Autodesk Fusion 360 part; units mm, degrees
(part 6 of 7)
ref_plane "WorkPlane2" through (0, 0, 38) normal (0, 0, 1) x (1, 0, 0) in component "REFERENCE wall bracket M5x8 100"
sketch "Shank sketch (5)" plane through (0, 0, 38) normal (0, 0, 1) x (1, 0, 0) in component "REFERENCE wall bracket M5x8 100"
  circle A0 centre (228, 52) radius 2.5
  dimension "d2338" = 228
  dimension "d2339" = 52
  dimension "d2340" = 5
  measures "d2338" horizontal distance of origin A0.centre
  measures "d2339" vertical distance of origin A0.centre
  measures "d2340" diameter of A0
extrude "Shank''''" add sketch "Shank sketch (5)" against normal blind 8 bodies 106 in component "REFERENCE wall bracket M5x8 100"
ref_plane "WorkPlane1" through (0, 0, 29) normal (0, 0, 1) x (1, 0, 0) in component "REFERENCE wall bracket T nut 100"
sketch "Nut sketch (5)" plane through (0, 0, 29) normal (0, 0, 1) x (1, 0, 0) in component "REFERENCE wall bracket T nut 100"
  line L0 (223.2, 47.2) -> (232.8, 47.2)
  line L1 (232.8, 47.2) -> (232.8, 56.8)
  line L2 (232.8, 56.8) -> (223.2, 56.8)
  line L3 (223.2, 56.8) -> (223.2, 47.2)
  dimension "d2345" = 223.2
  dimension "d2346" = 47.2
  dimension "d2347" = 9.6
  dimension "d2348" = 9.6
  constraint horizontal L0
  constraint vertical L1
  constraint horizontal L2
  constraint vertical L3
  measures "d2345" horizontal distance of origin L0.start
  measures "d2346" vertical distance of origin L0.start
  measures "d2347" horizontal distance of L0.start L0.end
  measures "d2348" vertical distance of L0.end L1.end
extrude "Nut''''" add sketch "Nut sketch (5)" along normal blind 4 separate body makes body 107 in component "REFERENCE wall bracket T nut 100"
ref_plane "WorkPlane2" through (0, 0, 29) normal (0, 0, 1) x (1, 0, 0) in component "REFERENCE wall bracket T nut 100"
sketch "Thread envelope sketch (28)" plane through (0, 0, 29) normal (0, 0, 1) x (1, 0, 0) in component "REFERENCE wall bracket T nut 100"
  circle A0 centre (228, 52) radius 2.6
  dimension "d2353" = 228
  dimension "d2354" = 52
  dimension "d2355" = 5.2
  measures "d2353" horizontal distance of origin A0.centre
  measures "d2354" vertical distance of origin A0.centre
  measures "d2355" diameter of A0
extrude "Thread envelope'''''''''''''''''''''''''''" cut sketch "Thread envelope sketch (28)" along normal blind 4 bodies 106 in component "REFERENCE wall bracket M5x8 100"
extrude "Extrude2'''''''''''''''''''''''''''" cut sketch "Thread envelope sketch (28)" along normal blind 4 bodies 107 in component "REFERENCE wall bracket T nut 100"
ref_plane "WorkPlane6" through (0, 0, 35) normal (0, 0, 1) x (1, 0, 0) in component "METAL wall standoff 10 - welded or machined"
sketch "Rail attachment clearance sketch (1) (3)" plane through (0, 0, 35) normal (0, 0, 1) x (1, 0, 0) in component "METAL wall standoff 10 - welded or machined"
  circle A0 centre (228, 68) radius 2.75
  dimension "d2362" = 228
  dimension "d2363" = 68
  dimension "d2364" = 5.5
  measures "d2362" horizontal distance of origin A0.centre
  measures "d2363" vertical distance of origin A0.centre
  measures "d2364" diameter of A0
extrude "Rail attachment clearance (1)''" cut sketch "Rail attachment clearance sketch (1) (3)" along normal blind 3 bodies 105 in component "METAL wall standoff 10 - welded or machined"
ref_plane "WorkPlane1" through (0, 0, 38) normal (0, 0, 1) x (1, 0, 0) in component "REFERENCE wall bracket M5x8 101"
sketch "Head sketch (6)" plane through (0, 0, 38) normal (0, 0, 1) x (1, 0, 0) in component "REFERENCE wall bracket M5x8 101"
  circle A0 centre (228, 68) radius 4.75
  dimension "d2369" = 228
  dimension "d2370" = 68
  dimension "d2371" = 9.5
  measures "d2369" horizontal distance of origin A0.centre
  measures "d2370" vertical distance of origin A0.centre
  measures "d2371" diameter of A0
extrude "Head'''''" add sketch "Head sketch (6)" along normal blind 3 separate body makes body 108 in component "REFERENCE wall bracket M5x8 101"
ref_plane "WorkPlane2" through (0, 0, 38) normal (0, 0, 1) x (1, 0, 0) in component "REFERENCE wall bracket M5x8 101"
sketch "Shank sketch (6)" plane through (0, 0, 38) normal (0, 0, 1) x (1, 0, 0) in component "REFERENCE wall bracket M5x8 101"
  circle A0 centre (228, 68) radius 2.5
  dimension "d2376" = 228
  dimension "d2377" = 68
  dimension "d2378" = 5
  measures "d2376" horizontal distance of origin A0.centre
  measures "d2377" vertical distance of origin A0.centre
  measures "d2378" diameter of A0
extrude "Shank'''''" add sketch "Shank sketch (6)" against normal blind 8 bodies 108 in component "REFERENCE wall bracket M5x8 101"
ref_plane "WorkPlane1" through (0, 0, 29) normal (0, 0, 1) x (1, 0, 0) in component "REFERENCE wall bracket T nut 101"
sketch "Nut sketch (6)" plane through (0, 0, 29) normal (0, 0, 1) x (1, 0, 0) in component "REFERENCE wall bracket T nut 101"
  line L0 (223.2, 63.2) -> (232.8, 63.2)
  line L1 (232.8, 63.2) -> (232.8, 72.8)
  line L2 (232.8, 72.8) -> (223.2, 72.8)
  line L3 (223.2, 72.8) -> (223.2, 63.2)
  dimension "d2383" = 223.2
  dimension "d2384" = 63.2
  dimension "d2385" = 9.6
  dimension "d2386" = 9.6
  constraint horizontal L0
  constraint vertical L1
  constraint horizontal L2
  constraint vertical L3
  measures "d2383" horizontal distance of origin L0.start
  measures "d2384" vertical distance of origin L0.start
  measures "d2385" horizontal distance of L0.start L0.end
  measures "d2386" vertical distance of L0.end L1.end
extrude "Nut'''''" add sketch "Nut sketch (6)" along normal blind 4 separate body makes body 109 in component "REFERENCE wall bracket T nut 101"
ref_plane "WorkPlane2" through (0, 0, 29) normal (0, 0, 1) x (1, 0, 0) in component "REFERENCE wall bracket T nut 101"
sketch "Thread envelope sketch (29)" plane through (0, 0, 29) normal (0, 0, 1) x (1, 0, 0) in component "REFERENCE wall bracket T nut 101"
  circle A0 centre (228, 68) radius 2.6
  dimension "d2391" = 228
  dimension "d2392" = 68
  dimension "d2393" = 5.2
  measures "d2391" horizontal distance of origin A0.centre
  measures "d2392" vertical distance of origin A0.centre
  measures "d2393" diameter of A0
extrude "Thread envelope''''''''''''''''''''''''''''" cut sketch "Thread envelope sketch (29)" along normal blind 4 bodies 108 in component "REFERENCE wall bracket M5x8 101"
extrude "Extrude2''''''''''''''''''''''''''''" cut sketch "Thread envelope sketch (29)" along normal blind 4 bodies 109 in component "REFERENCE wall bracket T nut 101"
ref_plane "WorkPlane1" through (0, 0, 35) normal (0, 0, 1) x (1, 0, 0) in component "METAL wall standoff 11 - welded or machined"
sketch "Rail pad sketch (4)" plane through (0, 0, 35) normal (0, 0, 1) x (1, 0, 0) in component "METAL wall standoff 11 - welded or machined"
  line L0 (218, 165) -> (238, 165)
  line L1 (238, 165) -> (238, 195)
  line L2 (238, 195) -> (218, 195)
  line L3 (218, 195) -> (218, 165)
  dimension "d2400" = 218
  dimension "d2401" = 165
  dimension "d2402" = 20
  dimension "d2403" = 30
  constraint horizontal L0
  constraint vertical L1
  constraint horizontal L2
  constraint vertical L3
  measures "d2400" horizontal distance of origin L0.start
  measures "d2401" vertical distance of origin L0.start
  measures "d2402" horizontal distance of L0.start L0.end
  measures "d2403" vertical distance of L0.end L1.end
extrude "Rail pad'''" add sketch "Rail pad sketch (4)" along normal blind 3 separate body makes body 110 in component "METAL wall standoff 11 - welded or machined"
ref_plane "WorkPlane2" through (0, 0, 38) normal (0, 0, 1) x (1, 0, 0) in component "METAL wall standoff 11 - welded or machined"
sketch "Standoff web sketch (4)" plane through (0, 0, 38) normal (0, 0, 1) x (1, 0, 0) in component "METAL wall standoff 11 - welded or machined"
  line L0 (218, 165) -> (221, 165)
  line L1 (221, 165) -> (221, 195)
  line L2 (221, 195) -> (218, 195)
  line L3 (218, 195) -> (218, 165)
  dimension "d2408" = 218
  dimension "d2409" = 165
  dimension "d2410" = 3
  dimension "d2411" = 30
  constraint horizontal L0
  constraint vertical L1
  constraint horizontal L2
  constraint vertical L3
  measures "d2408" horizontal distance of origin L0.start
  measures "d2409" vertical distance of origin L0.start
  measures "d2410" horizontal distance of L0.start L0.end
  measures "d2411" vertical distance of L0.end L1.end
extrude "Standoff web'''" add sketch "Standoff web sketch (4)" along normal blind 4 bodies 110 in component "METAL wall standoff 11 - welded or machined"
ref_plane "WorkPlane3" through (0, 0, 42) normal (0, 0, 1) x (1, 0, 0) in component "METAL wall standoff 11 - welded or machined"
sketch "Wall foot sketch (4)" plane through (0, 0, 42) normal (0, 0, 1) x (1, 0, 0) in component "METAL wall standoff 11 - welded or machined"
  line L0 (196, 165) -> (221, 165)
  line L1 (221, 165) -> (221, 195)
  line L2 (221, 195) -> (196, 195)
  line L3 (196, 195) -> (196, 165)
  dimension "d2416" = 196
  dimension "d2417" = 165
  dimension "d2418" = 25
  dimension "d2419" = 30
  constraint horizontal L0
  constraint vertical L1
  constraint horizontal L2
  constraint vertical L3
  measures "d2416" horizontal distance of origin L0.start
  measures "d2417" vertical distance of origin L0.start
  measures "d2418" horizontal distance of L0.start L0.end
  measures "d2419" vertical distance of L0.end L1.end
extrude "Wall foot'''" add sketch "Wall foot sketch (4)" along normal blind 3 bodies 110 in component "METAL wall standoff 11 - welded or machined"
ref_plane "WorkPlane4" through (0, 0, 42) normal (0, 0, 1) x (1, 0, 0) in component "METAL wall standoff 11 - welded or machined"
sketch "Wall anchor interface sketch (4)" plane through (0, 0, 42) normal (0, 0, 1) x (1, 0, 0) in component "METAL wall standoff 11 - welded or machined"
  circle A0 centre (206, 180) radius 3.25
  dimension "d2424" = 206
  dimension "d2425" = 180
  dimension "d2426" = 6.5
  measures "d2424" horizontal distance of origin A0.centre
  measures "d2425" vertical distance of origin A0.centre
  measures "d2426" diameter of A0
extrude "Wall anchor interface'''" cut sketch "Wall anchor interface sketch (4)" along normal blind 3 bodies 110 in component "METAL wall standoff 11 - welded or machined"
ref_plane "WorkPlane5" through (0, 0, 35) normal (0, 0, 1) x (1, 0, 0) in component "METAL wall standoff 11 - welded or machined"
sketch "Rail attachment clearance sketch (4)" plane through (0, 0, 35) normal (0, 0, 1) x (1, 0, 0) in component "METAL wall standoff 11 - welded or machined"
  circle A0 centre (228, 172) radius 2.75
  dimension "d2431" = 228
  dimension "d2432" = 172
  dimension "d2433" = 5.5
  measures "d2431" horizontal distance of origin A0.centre
  measures "d2432" vertical distance of origin A0.centre
  measures "d2433" diameter of A0
extrude "Rail attachment clearance'''" cut sketch "Rail attachment clearance sketch (4)" along normal blind 3 bodies 110 in component "METAL wall standoff 11 - welded or machined"
ref_plane "WorkPlane1" through (0, 0, 38) normal (0, 0, 1) x (1, 0, 0) in component "REFERENCE wall bracket M5x8 110"
sketch "Head sketch (7)" plane through (0, 0, 38) normal (0, 0, 1) x (1, 0, 0) in component "REFERENCE wall bracket M5x8 110"
  circle A0 centre (228, 172) radius 4.75
  dimension "d2438" = 228
  dimension "d2439" = 172
  dimension "d2440" = 9.5
  measures "d2438" horizontal distance of origin A0.centre
  measures "d2439" vertical distance of origin A0.centre
  measures "d2440" diameter of A0
extrude "Head''''''" add sketch "Head sketch (7)" along normal blind 3 separate body makes body 111 in component "REFERENCE wall bracket M5x8 110"
ref_plane "WorkPlane2" through (0, 0, 38) normal (0, 0, 1) x (1, 0, 0) in component "REFERENCE wall bracket M5x8 110"
sketch "Shank sketch (7)" plane through (0, 0, 38) normal (0, 0, 1) x (1, 0, 0) in component "REFERENCE wall bracket M5x8 110"
  circle A0 centre (228, 172) radius 2.5
  dimension "d2445" = 228
  dimension "d2446" = 172
  dimension "d2447" = 5
  measures "d2445" horizontal distance of origin A0.centre
  measures "d2446" vertical distance of origin A0.centre
  measures "d2447" diameter of A0
extrude "Shank''''''" add sketch "Shank sketch (7)" against normal blind 8 bodies 111 in component "REFERENCE wall bracket M5x8 110"
ref_plane "WorkPlane1" through (0, 0, 29) normal (0, 0, 1) x (1, 0, 0) in component "REFERENCE wall bracket T nut 110"
sketch "Nut sketch (7)" plane through (0, 0, 29) normal (0, 0, 1) x (1, 0, 0) in component "REFERENCE wall bracket T nut 110"
  line L0 (223.2, 167.2) -> (232.8, 167.2)
  line L1 (232.8, 167.2) -> (232.8, 176.8)
  line L2 (232.8, 176.8) -> (223.2, 176.8)
  line L3 (223.2, 176.8) -> (223.2, 167.2)
  dimension "d2452" = 223.2
  dimension "d2453" = 167.2
  dimension "d2454" = 9.6
  dimension "d2455" = 9.6
  constraint horizontal L0
  constraint vertical L1
  constraint horizontal L2
  constraint vertical L3
  measures "d2452" horizontal distance of origin L0.start
  measures "d2453" vertical distance of origin L0.start
  measures "d2454" horizontal distance of L0.start L0.end
  measures "d2455" vertical distance of L0.end L1.end
extrude "Nut''''''" add sketch "Nut sketch (7)" along normal blind 4 separate body makes body 112 in component "REFERENCE wall bracket T nut 110"
ref_plane "WorkPlane2" through (0, 0, 29) normal (0, 0, 1) x (1, 0, 0) in component "REFERENCE wall bracket T nut 110"
sketch "Thread envelope sketch (30)" plane through (0, 0, 29) normal (0, 0, 1) x (1, 0, 0) in component "REFERENCE wall bracket T nut 110"
  circle A0 centre (228, 172) radius 2.6
  dimension "d2460" = 228
  dimension "d2461" = 172
  dimension "d2462" = 5.2
  measures "d2460" horizontal distance of origin A0.centre
  measures "d2461" vertical distance of origin A0.centre
  measures "d2462" diameter of A0
extrude "Thread envelope'''''''''''''''''''''''''''''" cut sketch "Thread envelope sketch (30)" along normal blind 4 bodies 111 in component "REFERENCE wall bracket M5x8 110"
extrude "Extrude2'''''''''''''''''''''''''''''" cut sketch "Thread envelope sketch (30)" along normal blind 4 bodies 112 in component "REFERENCE wall bracket T nut 110"
ref_plane "WorkPlane6" through (0, 0, 35) normal (0, 0, 1) x (1, 0, 0) in component "METAL wall standoff 11 - welded or machined"
sketch "Rail attachment clearance sketch (1) (4)" plane through (0, 0, 35) normal (0, 0, 1) x (1, 0, 0) in component "METAL wall standoff 11 - welded or machined"
  circle A0 centre (228, 188) radius 2.75
  dimension "d2469" = 228
  dimension "d2470" = 188
  dimension "d2471" = 5.5
  measures "d2469" horizontal distance of origin A0.centre
  measures "d2470" vertical distance of origin A0.centre
  measures "d2471" diameter of A0
extrude "Rail attachment clearance (1)'''" cut sketch "Rail attachment clearance sketch (1) (4)" along normal blind 3 bodies 110 in component "METAL wall standoff 11 - welded or machined"
ref_plane "WorkPlane1" through (0, 0, 38) normal (0, 0, 1) x (1, 0, 0) in component "REFERENCE wall bracket M5x8 111"
sketch "Head sketch (8)" plane through (0, 0, 38) normal (0, 0, 1) x (1, 0, 0) in component "REFERENCE wall bracket M5x8 111"
  circle A0 centre (228, 188) radius 4.75
  dimension "d2476" = 228
  dimension "d2477" = 188
  dimension "d2478" = 9.5
  measures "d2476" horizontal distance of origin A0.centre
  measures "d2477" vertical distance of origin A0.centre
  measures "d2478" diameter of A0
extrude "Head'''''''" add sketch "Head sketch (8)" along normal blind 3 separate body makes body 113 in component "REFERENCE wall bracket M5x8 111"
ref_plane "WorkPlane2" through (0, 0, 38) normal (0, 0, 1) x (1, 0, 0) in component "REFERENCE wall bracket M5x8 111"
sketch "Shank sketch (8)" plane through (0, 0, 38) normal (0, 0, 1) x (1, 0, 0) in component "REFERENCE wall bracket M5x8 111"
  circle A0 centre (228, 188) radius 2.5
  dimension "d2483" = 228
  dimension "d2484" = 188
  dimension "d2485" = 5
  measures "d2483" horizontal distance of origin A0.centre
  measures "d2484" vertical distance of origin A0.centre
  measures "d2485" diameter of A0
extrude "Shank'''''''" add sketch "Shank sketch (8)" against normal blind 8 bodies 113 in component "REFERENCE wall bracket M5x8 111"
ref_plane "WorkPlane1" through (0, 0, 29) normal (0, 0, 1) x (1, 0, 0) in component "REFERENCE wall bracket T nut 111"
sketch "Nut sketch (8)" plane through (0, 0, 29) normal (0, 0, 1) x (1, 0, 0) in component "REFERENCE wall bracket T nut 111"
  line L0 (223.2, 183.2) -> (232.8, 183.2)
  line L1 (232.8, 183.2) -> (232.8, 192.8)
  line L2 (232.8, 192.8) -> (223.2, 192.8)
  line L3 (223.2, 192.8) -> (223.2, 183.2)
  dimension "d2490" = 223.2
  dimension "d2491" = 183.2
  dimension "d2492" = 9.6
  dimension "d2493" = 9.6
  constraint horizontal L0
  constraint vertical L1
  constraint horizontal L2
  constraint vertical L3
  measures "d2490" horizontal distance of origin L0.start
  measures "d2491" vertical distance of origin L0.start
  measures "d2492" horizontal distance of L0.start L0.end
  measures "d2493" vertical distance of L0.end L1.end
extrude "Nut'''''''" add sketch "Nut sketch (8)" along normal blind 4 separate body makes body 114 in component "REFERENCE wall bracket T nut 111"
ref_plane "WorkPlane2" through (0, 0, 29) normal (0, 0, 1) x (1, 0, 0) in component "REFERENCE wall bracket T nut 111"
sketch "Thread envelope sketch (31)" plane through (0, 0, 29) normal (0, 0, 1) x (1, 0, 0) in component "REFERENCE wall bracket T nut 111"
  circle A0 centre (228, 188) radius 2.6
  dimension "d2498" = 228
  dimension "d2499" = 188
  dimension "d2500" = 5.2
  measures "d2498" horizontal distance of origin A0.centre
  measures "d2499" vertical distance of origin A0.centre
  measures "d2500" diameter of A0
extrude "Thread envelope''''''''''''''''''''''''''''''" cut sketch "Thread envelope sketch (31)" along normal blind 4 bodies 113 in component "REFERENCE wall bracket M5x8 111"
extrude "Extrude2''''''''''''''''''''''''''''''" cut sketch "Thread envelope sketch (31)" along normal blind 4 bodies 114 in component "REFERENCE wall bracket T nut 111"
component "Panel lower left" placed x (1, 0, 0) y (0, 1, 0) z (0, 0, 1) at (0, 0, 0)
component "Panel lower right" placed x (1, 0, 0) y (0, 1, 0) z (0, 0, 1) at (0, 0, 0)
component "Panel upper left" placed x (1, 0, 0) y (0, 1, 0) z (0, 0, 1) at (0, 0, 0)
component "Panel upper right" placed x (1, 0, 0) y (0, 1, 0) z (0, 0, 1) at (0, 0, 0)
component "PRINT horizontal alignment key L" placed x (1, 0, 0) y (0, 1, 0) z (0, 0, 1) at (0, 0, 0)
component "PRINT horizontal alignment key R" placed x (1, 0, 0) y (0, 1, 0) z (0, 0, 1) at (0, 0, 0)
component "PRINT vertical alignment key B" placed x (1, 0, 0) y (0, 1, 0) z (0, 0, 1) at (0, 0, 0)
component "PRINT vertical alignment key T" placed x (1, 0, 0) y (0, 1, 0) z (0, 0, 1) at (0, 0, 0)
component "Vertical rail 0 - nominal 2020 slot-6 envelope" placed x (1, 0, 0) y (0, 1, 0) z (0, 0, 1) at (0, 0, 0)
component "Vertical rail 1 - nominal 2020 slot-6 envelope" placed x (1, 0, 0) y (0, 1, 0) z (0, 0, 1) at (0, 0, 0)
component "Vertical rail 2 - nominal 2020 slot-6 envelope" placed x (1, 0, 0) y (0, 1, 0) z (0, 0, 1) at (0, 0, 0)
component "Horizontal tie 00 - nominal 2020 slot-6 envelope" placed x (1, 0, 0) y (0, 1, 0) z (0, 0, 1) at (0, 0, 0)
component "Horizontal tie 10 - nominal 2020 slot-6 envelope" placed x (1, 0, 0) y (0, 1, 0) z (0, 0, 1) at (0, 0, 0)
component "Horizontal tie 01 - nominal 2020 slot-6 envelope" placed x (1, 0, 0) y (0, 1, 0) z (0, 0, 1) at (0, 0, 0)
component "Horizontal tie 11 - nominal 2020 slot-6 envelope" placed x (1, 0, 0) y (0, 1, 0) z (0, 0, 1) at (0, 0, 0)
component "METAL cap 00" placed x (1, 0, 0) y (0, 1, 0) z (0, 0, 1) at (0, 0, 0)
component "PRINT rear bearing seat 00" placed x (1, 0, 0) y (0, 1, 0) z (0, 0, 1) at (0, 0, 0)
component "METAL stepped compression spacer 00" placed x (1, 0, 0) y (0, 1, 0) z (0, 0, 1) at (0, 0, 0)
component "REFERENCE M5 screw 00 - length follows stack" placed x (1, 0, 0) y (0, 1, 0) z (0, 0, 1) at (0, 0, 0)
component "REFERENCE M5 slot-6 T nut 00" placed x (1, 0, 0) y (0, 1, 0) z (0, 0, 1) at (0, 0, 0)
component "METAL cap 01" placed x (1, 0, 0) y (0, 1, 0) z (0, 0, 1) at (0, 0, 0)
component "PRINT rear bearing seat 01" placed x (1, 0, 0) y (0, 1, 0) z (0, 0, 1) at (0, 0, 0)
component "METAL stepped compression spacer 01" placed x (1, 0, 0) y (0, 1, 0) z (0, 0, 1) at (0, 0, 0)
component "REFERENCE M5 screw 01 - length follows stack" placed x (1, 0, 0) y (0, 1, 0) z (0, 0, 1) at (0, 0, 0)
component "REFERENCE M5 slot-6 T nut 01" placed x (1, 0, 0) y (0, 1, 0) z (0, 0, 1) at (0, 0, 0)
component "METAL cap 02" placed x (1, 0, 0) y (0, 1, 0) z (0, 0, 1) at (0, 0, 0)
component "PRINT rear bearing seat 02" placed x (1, 0, 0) y (0, 1, 0) z (0, 0, 1) at (0, 0, 0)
component "METAL stepped compression spacer 02" placed x (1, 0, 0) y (0, 1, 0) z (0, 0, 1) at (0, 0, 0)
component "REFERENCE M5 screw 02 - length follows stack" placed x (1, 0, 0) y (0, 1, 0) z (0, 0, 1) at (0, 0, 0)
component "REFERENCE M5 slot-6 T nut 02" placed x (1, 0, 0) y (0, 1, 0) z (0, 0, 1) at (0, 0, 0)
component "METAL cap 10" placed x (1, 0, 0) y (0, 1, 0) z (0, 0, 1) at (0, 0, 0)
component "PRINT rear bearing seat 10" placed x (1, 0, 0) y (0, 1, 0) z (0, 0, 1) at (0, 0, 0)
component "METAL stepped compression spacer 10" placed x (1, 0, 0) y (0, 1, 0) z (0, 0, 1) at (0, 0, 0)
component "REFERENCE M5 screw 10 - length follows stack" placed x (1, 0, 0) y (0, 1, 0) z (0, 0, 1) at (0, 0, 0)
component "REFERENCE M5 slot-6 T nut 10" placed x (1, 0, 0) y (0, 1, 0) z (0, 0, 1) at (0, 0, 0)
component "METAL cap 11" placed x (1, 0, 0) y (0, 1, 0) z (0, 0, 1) at (0, 0, 0)
component "PRINT rear bearing seat 11" placed x (1, 0, 0) y (0, 1, 0) z (0, 0, 1) at (0, 0, 0)
component "METAL stepped compression spacer 11" placed x (1, 0, 0) y (0, 1, 0) z (0, 0, 1) at (0, 0, 0)
component "REFERENCE M5 screw 11 - length follows stack" placed x (1, 0, 0) y (0, 1, 0) z (0, 0, 1) at (0, 0, 0)
component "REFERENCE M5 slot-6 T nut 11" placed x (1, 0, 0) y (0, 1, 0) z (0, 0, 1) at (0, 0, 0)
component "METAL cap 12" placed x (1, 0, 0) y (0, 1, 0) z (0, 0, 1) at (0, 0, 0)
component "PRINT rear bearing seat 12" placed x (1, 0, 0) y (0, 1, 0) z (0, 0, 1) at (0, 0, 0)
component "METAL stepped compression spacer 12" placed x (1, 0, 0) y (0, 1, 0) z (0, 0, 1) at (0, 0, 0)
component "REFERENCE M5 screw 12 - length follows stack" placed x (1, 0, 0) y (0, 1, 0) z (0, 0, 1) at (0, 0, 0)
component "REFERENCE M5 slot-6 T nut 12" placed x (1, 0, 0) y (0, 1, 0) z (0, 0, 1) at (0, 0, 0)
component "METAL cap 20" placed x (1, 0, 0) y (0, 1, 0) z (0, 0, 1) at (0, 0, 0)
component "PRINT rear bearing seat 20" placed x (1, 0, 0) y (0, 1, 0) z (0, 0, 1) at (0, 0, 0)
component "METAL stepped compression spacer 20" placed x (1, 0, 0) y (0, 1, 0) z (0, 0, 1) at (0, 0, 0)
component "REFERENCE M5 screw 20 - length follows stack" placed x (1, 0, 0) y (0, 1, 0) z (0, 0, 1) at (0, 0, 0)
component "REFERENCE M5 slot-6 T nut 20" placed x (1, 0, 0) y (0, 1, 0) z (0, 0, 1) at (0, 0, 0)
component "METAL cap 21" placed x (1, 0, 0) y (0, 1, 0) z (0, 0, 1) at (0, 0, 0)
component "PRINT rear bearing seat 21" placed x (1, 0, 0) y (0, 1, 0) z (0, 0, 1) at (0, 0, 0)
component "METAL stepped compression spacer 21" placed x (1, 0, 0) y (0, 1, 0) z (0, 0, 1) at (0, 0, 0)
component "REFERENCE M5 screw 21 - length follows stack" placed x (1, 0, 0) y (0, 1, 0) z (0, 0, 1) at (0, 0, 0)
component "REFERENCE M5 slot-6 T nut 21" placed x (1, 0, 0) y (0, 1, 0) z (0, 0, 1) at (0, 0, 0)
component "METAL cap 22" placed x (1, 0, 0) y (0, 1, 0) z (0, 0, 1) at (0, 0, 0)
component "PRINT rear bearing seat 22" placed x (1, 0, 0) y (0, 1, 0) z (0, 0, 1) at (0, 0, 0)
component "METAL stepped compression spacer 22" placed x (1, 0, 0) y (0, 1, 0) z (0, 0, 1) at (0, 0, 0)
component "REFERENCE M5 screw 22 - length follows stack" placed x (1, 0, 0) y (0, 1, 0) z (0, 0, 1) at (0, 0, 0)
component "REFERENCE M5 slot-6 T nut 22" placed x (1, 0, 0) y (0, 1, 0) z (0, 0, 1) at (0, 0, 0)
component "METAL rear splice plate 00" placed x (1, 0, 0) y (0, 1, 0) z (0, 0, 1) at (0, 0, 0)
component "REFERENCE rear join screw 000" placed x (1, 0, 0) y (0, 1, 0) z (0, 0, 1) at (0, 0, 0)
component "REFERENCE rear T nut 000" placed x (1, 0, 0) y (0, 1, 0) z (0, 0, 1) at (0, 0, 0)
component "REFERENCE rear join screw 001" placed x (1, 0, 0) y (0, 1, 0) z (0, 0, 1) at (0, 0, 0)
component "REFERENCE rear T nut 001" placed x (1, 0, 0) y (0, 1, 0) z (0, 0, 1) at (0, 0, 0)
component "METAL rear splice plate 10" placed x (1, 0, 0) y (0, 1, 0) z (0, 0, 1) at (0, 0, 0)
component "REFERENCE rear join screw 100" placed x (1, 0, 0) y (0, 1, 0) z (0, 0, 1) at (0, 0, 0)
component "REFERENCE rear T nut 100" placed x (1, 0, 0) y (0, 1, 0) z (0, 0, 1) at (0, 0, 0)
component "REFERENCE rear join screw 101" placed x (1, 0, 0) y (0, 1, 0) z (0, 0, 1) at (0, 0, 0)
component "REFERENCE rear T nut 101" placed x (1, 0, 0) y (0, 1, 0) z (0, 0, 1) at (0, 0, 0)
component "REFERENCE rear join screw 102" placed x (1, 0, 0) y (0, 1, 0) z (0, 0, 1) at (0, 0, 0)
component "REFERENCE rear T nut 102" placed x (1, 0, 0) y (0, 1, 0) z (0, 0, 1) at (0, 0, 0)
component "METAL rear splice plate 20" placed x (1, 0, 0) y (0, 1, 0) z (0, 0, 1) at (0, 0, 0)
component "REFERENCE rear join screw 200" placed x (1, 0, 0) y (0, 1, 0) z (0, 0, 1) at (0, 0, 0)
component "REFERENCE rear T nut 200" placed x (1, 0, 0) y (0, 1, 0) z (0, 0, 1) at (0, 0, 0)
component "REFERENCE rear join screw 201" placed x (1, 0, 0) y (0, 1, 0) z (0, 0, 1) at (0, 0, 0)
component "REFERENCE rear T nut 201" placed x (1, 0, 0) y (0, 1, 0) z (0, 0, 1) at (0, 0, 0)
component "METAL rear splice plate 01" placed x (1, 0, 0) y (0, 1, 0) z (0, 0, 1) at (0, 0, 0)
component "REFERENCE rear join screw 010" placed x (1, 0, 0) y (0, 1, 0) z (0, 0, 1) at (0, 0, 0)
component "REFERENCE rear T nut 010" placed x (1, 0, 0) y (0, 1, 0) z (0, 0, 1) at (0, 0, 0)
component "REFERENCE rear join screw 011" placed x (1, 0, 0) y (0, 1, 0) z (0, 0, 1) at (0, 0, 0)
component "REFERENCE rear T nut 011" placed x (1, 0, 0) y (0, 1, 0) z (0, 0, 1) at (0, 0, 0)
component "METAL rear splice plate 11" placed x (1, 0, 0) y (0, 1, 0) z (0, 0, 1) at (0, 0, 0)
component "REFERENCE rear join screw 110" placed x (1, 0, 0) y (0, 1, 0) z (0, 0, 1) at (0, 0, 0)
component "REFERENCE rear T nut 110" placed x (1, 0, 0) y (0, 1, 0) z (0, 0, 1) at (0, 0, 0)
component "REFERENCE rear join screw 111" placed x (1, 0, 0) y (0, 1, 0) z (0, 0, 1) at (0, 0, 0)
component "REFERENCE rear T nut 111" placed x (1, 0, 0) y (0, 1, 0) z (0, 0, 1) at (0, 0, 0)
component "REFERENCE rear join screw 112" placed x (1, 0, 0) y (0, 1, 0) z (0, 0, 1) at (0, 0, 0)
component "REFERENCE rear T nut 112" placed x (1, 0, 0) y (0, 1, 0) z (0, 0, 1) at (0, 0, 0)
component "METAL rear splice plate 21" placed x (1, 0, 0) y (0, 1, 0) z (0, 0, 1) at (0, 0, 0)
component "REFERENCE rear join screw 210" placed x (1, 0, 0) y (0, 1, 0) z (0, 0, 1) at (0, 0, 0)
component "REFERENCE rear T nut 210" placed x (1, 0, 0) y (0, 1, 0) z (0, 0, 1) at (0, 0, 0)
component "REFERENCE rear join screw 211" placed x (1, 0, 0) y (0, 1, 0) z (0, 0, 1) at (0, 0, 0)
component "REFERENCE rear T nut 211" placed x (1, 0, 0) y (0, 1, 0) z (0, 0, 1) at (0, 0, 0)
component "METAL wall standoff 00 - welded or machined" placed x (1, 0, 0) y (0, 1, 0) z (0, 0, 1) at (0, 0, 0)
component "REFERENCE wall bracket M5x8 000" placed x (1, 0, 0) y (0, 1, 0) z (0, 0, 1) at (0, 0, 0)
component "REFERENCE wall bracket T nut 000" placed x (1, 0, 0) y (0, 1, 0) z (0, 0, 1) at (0, 0, 0)
component "REFERENCE wall bracket M5x8 001" placed x (1, 0, 0) y (0, 1, 0) z (0, 0, 1) at (0, 0, 0)
component "REFERENCE wall bracket T nut 001" placed x (1, 0, 0) y (0, 1, 0) z (0, 0, 1) at (0, 0, 0)
component "METAL wall standoff 01 - welded or machined" placed x (1, 0, 0) y (0, 1, 0) z (0, 0, 1) at (0, 0, 0)
component "REFERENCE wall bracket M5x8 010" placed x (1, 0, 0) y (0, 1, 0) z (0, 0, 1) at (0, 0, 0)
component "REFERENCE wall bracket T nut 010" placed x (1, 0, 0) y (0, 1, 0) z (0, 0, 1) at (0, 0, 0)
component "REFERENCE wall bracket M5x8 011" placed x (1, 0, 0) y (0, 1, 0) z (0, 0, 1) at (0, 0, 0)
component "REFERENCE wall bracket T nut 011" placed x (1, 0, 0) y (0, 1, 0) z (0, 0, 1) at (0, 0, 0)
component "METAL wall standoff 10 - welded or machined" placed x (1, 0, 0) y (0, 1, 0) z (0, 0, 1) at (0, 0, 0)
component "REFERENCE wall bracket M5x8 100" placed x (1, 0, 0) y (0, 1, 0) z (0, 0, 1) at (0, 0, 0)
component "REFERENCE wall bracket T nut 100" placed x (1, 0, 0) y (0, 1, 0) z (0, 0, 1) at (0, 0, 0)
component "REFERENCE wall bracket M5x8 101" placed x (1, 0, 0) y (0, 1, 0) z (0, 0, 1) at (0, 0, 0)
component "REFERENCE wall bracket T nut 101" placed x (1, 0, 0) y (0, 1, 0) z (0, 0, 1) at (0, 0, 0)
component "METAL wall standoff 11 - welded or machined" placed x (1, 0, 0) y (0, 1, 0) z (0, 0, 1) at (0, 0, 0)
component "REFERENCE wall bracket M5x8 110" placed x (1, 0, 0) y (0, 1, 0) z (0, 0, 1) at (0, 0, 0)
component "REFERENCE wall bracket T nut 110" placed x (1, 0, 0) y (0, 1, 0) z (0, 0, 1) at (0, 0, 0)
component "REFERENCE wall bracket M5x8 111" placed x (1, 0, 0) y (0, 1, 0) z (0, 0, 1) at (0, 0, 0)
component "REFERENCE wall bracket T nut 111" placed x (1, 0, 0) y (0, 1, 0) z (0, 0, 1) at (0, 0, 0)
equation "columns = 6" comment "Even integer 4..14; each cell is 20 mm"
equation "rows = 6" comment "Even integer 4..14"
equation "pitch = 20 mm" comment "Keep for dense SKADIS compatible lattice"
equation "panelWidth = columns * pitch" comment "Nominal module pitch X"
equation "panelHeight = rows * pitch" comment "Nominal module pitch Y"
equation "seamGap = 0.2 mm" comment "Physical envelope shrinks around fixed lattice"
equation "boardThickness = 5 mm" comment "Fit-test with real hooks"
equation "slotWidth = 5 mm" comment "Minimum throat width"
equation "slotHeight = 15 mm" comment "Minimum throat height"
equation "entryRadius = 0.4 mm" comment "Front slot and perimeter edge rounding"
equation "cornerRadius = 6 mm" comment "Plan-view panel corner rounding"
equation "hookClearance = 10 mm" comment "PROVISIONAL: board rear to front of extrusion"
equation "frameZ = boardThickness + hookClearance" comment "Front extrusion datum"
equation "mountInset = 12 mm" comment "Exterior node inset from outside module edge"
equation "mountBore = 8.4 mm" comment "Clearance around 8 mm metal shoulder"
equation "capDiameter = 18 mm" comment "Visible decorative mounting disk"
equation "capThickness = 2 mm" comment "Metal clamping cap / washer"
equation "seatThickness = 2 mm" comment "Printed rear bearing washer"
equation "screwDiameter = 5 mm" comment "Nominal M5 reference, threads omitted"
equation "screwClearance = 5.5 mm" comment "Cap and spacer bore"
equation "keyWidth = 4 mm" comment "Registration key corridor width"
equation "keyThickness = 2 mm" comment "Rear removable key body"
equation "keyPegDiameter = 3 mm" comment "Rear locating peg"
equation "keySocketDiameter = 3.4 mm" comment "0.2 mm radial starting fit"
equation "keyPegHeight = 0.8 mm" comment "Peg penetration"
equation "keySocketDepth = 1 mm" comment "Blind locating pocket"
equation "llLeft = 1" comment "0 internal / 1 finished; full cell border and inset mounting"
equation "llRight = 0" comment "0 internal / 1 finished; full cell border and inset mounting"
equation "llBottom = 1" comment "0 internal / 1 finished; full cell border and inset mounting"
equation "llTop = 0" comment "0 internal / 1 finished; full cell border and inset mounting"
equation "d31 = abs(( 0 mm ) + seamGap / 2)"
equation "d32 = abs(( 0 mm ) + seamGap / 2)"
equation "d33 = panelWidth - seamGap"
equation "d34 = panelHeight - seamGap"
equation "d35 = boardThickness"
equation "d38 = cornerRadius"
equation "d39 = slotWidth"
equation "d40 = slotHeight - slotWidth"
equation "d42 = pitch / 2"
equation "d43 = abs(( 0 mm ) + pitch / 4 + pitch * ( llLeft + 1 ))"
equation "d44 = abs(( ( 0 mm ) + pitch / 2 + pitch * llBottom ) - ( slotHeight - slotWidth ) / 2)"
equation "d45 = boardThickness"
equation "d47 = columns - llLeft - llRight - 1"
equation "d48 = rows - llBottom - llTop"
equation "d49 = pitch"
equation "d50 = pitch"
equation "d51 = slotWidth"
equation "d52 = slotHeight - slotWidth"
equation "d54 = pitch / 2"
equation "d55 = abs(( 0 mm ) + pitch / 4 + pitch * llLeft)"
equation "d56 = abs(( ( 0 mm ) + 3 * pitch / 2 + pitch * llBottom ) - ( slotHeight - slotWidth ) / 2)"
equation "d57 = boardThickness"
equation "d60 = rows - llBottom - llTop - 2"
equation "d61 = pitch"
equation "d62 = pitch"
equation "d63 = slotWidth"
equation "d64 = slotHeight - slotWidth"
equation "d66 = pitch / 2"
equation "d67 = abs(( 0 mm ) + 3 * pitch / 4 + pitch * llLeft)"
equation "d68 = abs(( ( 0 mm ) + pitch * llBottom ) - ( slotHeight - slotWidth ) / 2)"
equation "d69 = boardThickness"
equation "d71 = columns - llLeft - llRight - 1"
equation "d72 = rows + 1 - llBottom - llTop"
equation "d73 = pitch"
equation "d74 = pitch"
equation "d75 = slotWidth"
equation "d76 = slotHeight - slotWidth"
equation "d78 = pitch / 2"
equation "d79 = abs(( 0 mm ) + panelWidth - pitch / 4 - pitch * llRight)"
equation "d80 = abs(( ( 0 mm ) + pitch + pitch * llBottom ) - ( slotHeight - slotWidth ) / 2)"
equation "d81 = boardThickness"
equation "d84 = rows - 1 - llBottom - llTop"
equation "d85 = pitch"
equation "d86 = pitch"
equation "d87 = abs(( 0 mm ) + mountInset * llLeft)"
equation "d88 = abs(( 0 mm ) + mountInset * llBottom)"
equation "d89 = mountBore"
equation "d90 = boardThickness"
equation "d92 = abs(( 0 mm ) + mountInset * llLeft)"
equation "d93 = abs(( 0 mm ) + panelHeight - mountInset * llTop)"
equation "d94 = mountBore"
equation "d95 = boardThickness"
equation "d97 = abs(( 0 mm ) + panelWidth - mountInset * llRight)"
equation "d98 = abs(( 0 mm ) + mountInset * llBottom)"
equation "d99 = mountBore"
equation "d100 = boardThickness"
equation "d102 = abs(( 0 mm ) + panelWidth - mountInset * llRight)"
equation "d103 = abs(( 0 mm ) + panelHeight - mountInset * llTop)"
equation "d104 = mountBore"
equation "d105 = boardThickness"
equation "d108 = entryRadius"
equation "d109 = boardThickness"
equation "d111 = abs(( 0 mm ) + panelWidth - pitch / 4)"
equation "d112 = abs(( 0 mm ) + panelHeight / 2 + pitch / 2)"
equation "d113 = keySocketDiameter"
equation "d114 = -keySocketDepth"
equation "d116 = boardThickness"
equation "d118 = abs(( 0 mm ) + panelWidth / 2 + pitch / 2)"
equation "d119 = abs(( 0 mm ) + panelHeight - pitch / 4)"
equation "d120 = keySocketDiameter"
equation "d121 = -keySocketDepth"
equation "lrLeft = 0" comment "0 internal / 1 finished; full cell border and inset mounting"
equation "lrRight = 1" comment "0 internal / 1 finished; full cell border and inset mounting"
equation "lrBottom = 1" comment "0 internal / 1 finished; full cell border and inset mounting"
equation "lrTop = 0" comment "0 internal / 1 finished; full cell border and inset mounting"
equation "d127 = abs(( panelWidth ) + seamGap / 2)"
equation "d128 = abs(( 0 mm ) + seamGap / 2)"
equation "d129 = panelWidth - seamGap"
equation "d130 = panelHeight - seamGap"
equation "d131 = boardThickness"
equation "d134 = cornerRadius"
equation "d135 = slotWidth"
equation "d136 = slotHeight - slotWidth"
equation "d138 = pitch / 2"
equation "d139 = abs(( panelWidth ) + pitch / 4 + pitch * ( lrLeft + 1 ))"
equation "d140 = abs(( ( 0 mm ) + pitch / 2 + pitch * lrBottom ) - ( slotHeight - slotWidth ) / 2)"
equation "d141 = boardThickness"
equation "d143 = columns - lrLeft - lrRight - 1"
equation "d144 = rows - lrBottom - lrTop"
equation "d145 = pitch"
equation "d146 = pitch"
equation "d147 = slotWidth"
equation "d148 = slotHeight - slotWidth"
equation "d150 = pitch / 2"
equation "d151 = abs(( panelWidth ) + pitch / 4 + pitch * lrLeft)"
equation "d152 = abs(( ( 0 mm ) + 3 * pitch / 2 + pitch * lrBottom ) - ( slotHeight - slotWidth ) / 2)"
equation "d153 = boardThickness"
equation "d156 = rows - lrBottom - lrTop - 2"
equation "d157 = pitch"
equation "d158 = pitch"
equation "d159 = slotWidth"
equation "d160 = slotHeight - slotWidth"
equation "d162 = pitch / 2"
equation "d163 = abs(( panelWidth ) + 3 * pitch / 4 + pitch * lrLeft)"
equation "d164 = abs(( ( 0 mm ) + pitch * lrBottom ) - ( slotHeight - slotWidth ) / 2)"
equation "d165 = boardThickness"
equation "d167 = columns - lrLeft - lrRight - 1"
equation "d168 = rows + 1 - lrBottom - lrTop"
equation "d169 = pitch"
equation "d170 = pitch"
equation "d171 = slotWidth"
equation "d172 = slotHeight - slotWidth"
equation "d174 = pitch / 2"
equation "d175 = abs(( panelWidth ) + panelWidth - pitch / 4 - pitch * lrRight)"
equation "d176 = abs(( ( 0 mm ) + pitch + pitch * lrBottom ) - ( slotHeight - slotWidth ) / 2)"
equation "d177 = boardThickness"
equation "d180 = rows - 1 - lrBottom - lrTop"
equation "d181 = pitch"
equation "d182 = pitch"
equation "d183 = abs(( panelWidth ) + mountInset * lrLeft)"
equation "d184 = abs(( 0 mm ) + mountInset * lrBottom)"
equation "d185 = mountBore"
equation "d186 = boardThickness"
equation "d188 = abs(( panelWidth ) + mountInset * lrLeft)"
equation "d189 = abs(( 0 mm ) + panelHeight - mountInset * lrTop)"
equation "d190 = mountBore"
equation "d191 = boardThickness"
equation "d193 = abs(( panelWidth ) + panelWidth - mountInset * lrRight)"
equation "d194 = abs(( 0 mm ) + mountInset * lrBottom)"
equation "d195 = mountBore"
equation "d196 = boardThickness"
equation "d198 = abs(( panelWidth ) + panelWidth - mountInset * lrRight)"
equation "d199 = abs(( 0 mm ) + panelHeight - mountInset * lrTop)"
equation "d200 = mountBore"
equation "d201 = boardThickness"
equation "d204 = entryRadius"
equation "d205 = boardThickness"
equation "d207 = abs(( panelWidth ) + pitch / 4)"
equation "d208 = abs(( 0 mm ) + panelHeight / 2 + pitch)"
equation "d209 = keySocketDiameter"
equation "d210 = -keySocketDepth"
equation "d212 = boardThickness"
equation "d214 = abs(( panelWidth ) + panelWidth / 2 + pitch / 2)"
equation "d215 = abs(( 0 mm ) + panelHeight - pitch / 4)"
equation "d216 = keySocketDiameter"
equation "d217 = -keySocketDepth"
equation "ulLeft = 1" comment "0 internal / 1 finished; full cell border and inset mounting"
equation "ulRight = 0" comment "0 internal / 1 finished; full cell border and inset mounting"
equation "ulBottom = 0" comment "0 internal / 1 finished; full cell border and inset mounting"
equation "ulTop = 1" comment "0 internal / 1 finished; full cell border and inset mounting"
equation "d223 = abs(( 0 mm ) + seamGap / 2)"
equation "d224 = abs(( panelHeight ) + seamGap / 2)"
equation "d225 = panelWidth - seamGap"
equation "d226 = panelHeight - seamGap"
equation "d227 = boardThickness"
equation "d230 = cornerRadius"
equation "d231 = slotWidth"
equation "d232 = slotHeight - slotWidth"
equation "d234 = pitch / 2"
equation "d235 = abs(( 0 mm ) + pitch / 4 + pitch * ( ulLeft + 1 ))"
equation "d236 = abs(( ( panelHeight ) + pitch / 2 + pitch * ulBottom ) - ( slotHeight - slotWidth ) / 2)"
equation "d237 = boardThickness"
equation "d239 = columns - ulLeft - ulRight - 1"
equation "d240 = rows - ulBottom - ulTop"
equation "d241 = pitch"
equation "d242 = pitch"
equation "d243 = slotWidth"
equation "d244 = slotHeight - slotWidth"
equation "d246 = pitch / 2"
equation "d247 = abs(( 0 mm ) + pitch / 4 + pitch * ulLeft)"
equation "d248 = abs(( ( panelHeight ) + 3 * pitch / 2 + pitch * ulBottom ) - ( slotHeight - slotWidth ) / 2)"
equation "d249 = boardThickness"
equation "d252 = rows - ulBottom - ulTop - 2"
equation "d253 = pitch"
equation "d254 = pitch"
equation "d255 = slotWidth"
equation "d256 = slotHeight - slotWidth"
equation "d258 = pitch / 2"
equation "d259 = abs(( 0 mm ) + 3 * pitch / 4 + pitch * ulLeft)"
equation "d260 = abs(( ( panelHeight ) + pitch * ulBottom ) - ( slotHeight - slotWidth ) / 2)"
equation "d261 = boardThickness"
equation "d263 = columns - ulLeft - ulRight - 1"
equation "d264 = rows + 1 - ulBottom - ulTop"
equation "d265 = pitch"
equation "d266 = pitch"
equation "d267 = slotWidth"
equation "d268 = slotHeight - slotWidth"
equation "d270 = pitch / 2"
equation "d271 = abs(( 0 mm ) + panelWidth - pitch / 4 - pitch * ulRight)"
equation "d272 = abs(( ( panelHeight ) + pitch + pitch * ulBottom ) - ( slotHeight - slotWidth ) / 2)"
equation "d273 = boardThickness"
equation "d276 = rows - 1 - ulBottom - ulTop"
equation "d277 = pitch"
equation "d278 = pitch"
equation "d279 = abs(( 0 mm ) + mountInset * ulLeft)"
equation "d280 = abs(( panelHeight ) + mountInset * ulBottom)"
equation "d281 = mountBore"
equation "d282 = boardThickness"
equation "d284 = abs(( 0 mm ) + mountInset * ulLeft)"
equation "d285 = abs(( panelHeight ) + panelHeight - mountInset * ulTop)"
equation "d286 = mountBore"
equation "d287 = boardThickness"
equation "d289 = abs(( 0 mm ) + panelWidth - mountInset * ulRight)"
equation "d290 = abs(( panelHeight ) + mountInset * ulBottom)"
equation "d291 = mountBore"
equation "d292 = boardThickness"
equation "d294 = abs(( 0 mm ) + panelWidth - mountInset * ulRight)"
equation "d295 = abs(( panelHeight ) + panelHeight - mountInset * ulTop)"
equation "d296 = mountBore"
equation "d297 = boardThickness"
equation "d300 = entryRadius"
equation "d301 = boardThickness"
equation "d303 = abs(( 0 mm ) + panelWidth - pitch / 4)"
equation "d304 = abs(( panelHeight ) + panelHeight / 2 + pitch / 2)"
equation "d305 = keySocketDiameter"
equation "d306 = -keySocketDepth"
equation "d308 = boardThickness"
equation "d310 = abs(( 0 mm ) + panelWidth / 2 + pitch / 2)"
equation "d311 = abs(( panelHeight ) + pitch / 4)"
equation "d312 = keySocketDiameter"
equation "d313 = -keySocketDepth"
equation "urLeft = 0" comment "0 internal / 1 finished; full cell border and inset mounting"
equation "urRight = 1" comment "0 internal / 1 finished; full cell border and inset mounting"
equation "urBottom = 0" comment "0 internal / 1 finished; full cell border and inset mounting"
equation "urTop = 1" comment "0 internal / 1 finished; full cell border and inset mounting"
equation "d319 = abs(( panelWidth ) + seamGap / 2)"
equation "d320 = abs(( panelHeight ) + seamGap / 2)"
equation "d321 = panelWidth - seamGap"
equation "d322 = panelHeight - seamGap"
equation "d323 = boardThickness"
equation "d326 = cornerRadius"
equation "d327 = slotWidth"
equation "d328 = slotHeight - slotWidth"
equation "d330 = pitch / 2"
equation "d331 = abs(( panelWidth ) + pitch / 4 + pitch * ( urLeft + 1 ))"
equation "d332 = abs(( ( panelHeight ) + pitch / 2 + pitch * urBottom ) - ( slotHeight - slotWidth ) / 2)"
equation "d333 = boardThickness"
equation "d335 = columns - urLeft - urRight - 1"
equation "d336 = rows - urBottom - urTop"
equation "d337 = pitch"
equation "d338 = pitch"
equation "d339 = slotWidth"
equation "d340 = slotHeight - slotWidth"
equation "d342 = pitch / 2"
equation "d343 = abs(( panelWidth ) + pitch / 4 + pitch * urLeft)"
equation "d344 = abs(( ( panelHeight ) + 3 * pitch / 2 + pitch * urBottom ) - ( slotHeight - slotWidth ) / 2)"
equation "d345 = boardThickness"
equation "d348 = rows - urBottom - urTop - 2"
equation "d349 = pitch"
equation "d350 = pitch"
equation "d351 = slotWidth"
equation "d352 = slotHeight - slotWidth"
equation "d354 = pitch / 2"
equation "d355 = abs(( panelWidth ) + 3 * pitch / 4 + pitch * urLeft)"
equation "d356 = abs(( ( panelHeight ) + pitch * urBottom ) - ( slotHeight - slotWidth ) / 2)"
equation "d357 = boardThickness"
equation "d359 = columns - urLeft - urRight - 1"
equation "d360 = rows + 1 - urBottom - urTop"
equation "d361 = pitch"
equation "d362 = pitch"
equation "d363 = slotWidth"
equation "d364 = slotHeight - slotWidth"
equation "d366 = pitch / 2"
equation "d367 = abs(( panelWidth ) + panelWidth - pitch / 4 - pitch * urRight)"
equation "d368 = abs(( ( panelHeight ) + pitch + pitch * urBottom ) - ( slotHeight - slotWidth ) / 2)"
equation "d369 = boardThickness"
equation "d372 = rows - 1 - urBottom - urTop"
equation "d373 = pitch"
equation "d374 = pitch"
equation "d375 = abs(( panelWidth ) + mountInset * urLeft)"
equation "d376 = abs(( panelHeight ) + mountInset * urBottom)"
equation "d377 = mountBore"
equation "d378 = boardThickness"
equation "d380 = abs(( panelWidth ) + mountInset * urLeft)"
equation "d381 = abs(( panelHeight ) + panelHeight - mountInset * urTop)"
equation "d382 = mountBore"
equation "d383 = boardThickness"
equation "d385 = abs(( panelWidth ) + panelWidth - mountInset * urRight)"
equation "d386 = abs(( panelHeight ) + mountInset * urBottom)"
equation "d387 = mountBore"
equation "d388 = boardThickness"
equation "d390 = abs(( panelWidth ) + panelWidth - mountInset * urRight)"
equation "d391 = abs(( panelHeight ) + panelHeight - mountInset * urTop)"
equation "d392 = mountBore"
equation "d393 = boardThickness"
equation "d396 = entryRadius"
equation "d397 = boardThickness"
equation "d399 = abs(( panelWidth ) + pitch / 4)"
equation "d400 = abs(( panelHeight ) + panelHeight / 2 + pitch)"
equation "d401 = keySocketDiameter"
equation "d402 = -keySocketDepth"
equation "d404 = boardThickness"
equation "d406 = abs(( panelWidth ) + panelWidth / 2 + pitch / 2)"
equation "d407 = abs(( panelHeight ) + pitch / 4)"
equation "d408 = keySocketDiameter"
equation "d409 = -keySocketDepth"
equation "d411 = boardThickness"
equation "d413 = abs(panelWidth / 2 + pitch / 2 - keyWidth / 2)"
equation "d414 = abs(panelHeight - pitch / 4 - keyWidth / 2)"
equation "d415 = keyWidth"
equation "d416 = pitch / 2 + keyWidth"
equation "d417 = keyThickness"
equation "d419 = boardThickness"
equation "d421 = abs(panelWidth / 2 + pitch / 2)"
equation "d422 = abs(panelHeight - pitch / 4)"
equation "d423 = keyPegDiameter"
equation "d424 = -keyPegHeight"
equation "d426 = boardThickness"
equation "d428 = abs(panelWidth / 2 + pitch / 2)"
equation "d429 = abs(panelHeight + pitch / 4)"
equation "d430 = keyPegDiameter"
equation "d431 = -keyPegHeight"
equation "d433 = boardThickness"
equation "d435 = abs(3 * panelWidth / 2 + pitch / 2 - keyWidth / 2)"
equation "d436 = abs(panelHeight - pitch / 4 - keyWidth / 2)"
equation "d437 = keyWidth"
equation "d438 = pitch / 2 + keyWidth"
equation "d439 = keyThickness"
equation "d441 = boardThickness"
equation "d443 = abs(3 * panelWidth / 2 + pitch / 2)"
equation "d444 = abs(panelHeight - pitch / 4)"
equation "d445 = keyPegDiameter"
equation "d446 = -keyPegHeight"
equation "d448 = boardThickness"
equation "d450 = abs(3 * panelWidth / 2 + pitch / 2)"
equation "d451 = abs(panelHeight + pitch / 4)"
equation "d452 = keyPegDiameter"
equation "d453 = -keyPegHeight"
equation "d455 = boardThickness"
equation "d457 = abs(panelWidth - keyWidth / 2)"
equation "d458 = abs(panelHeight / 2 + 3 * pitch / 4 - pitch / 4 - keyWidth / 2)"
equation "d459 = keyWidth"
equation "d460 = pitch / 2 + keyWidth"
equation "d461 = keyThickness"
equation "d463 = boardThickness"
equation "d465 = abs(panelWidth - pitch / 4 - keyWidth / 2)"
equation "d466 = abs(panelHeight / 2 + 3 * pitch / 4 - pitch / 4 - keyWidth / 2)"
equation "d467 = pitch / 4 + keyWidth"
equation "d468 = keyWidth"
equation "d469 = keyThickness"
equation "d471 = boardThickness"
equation "d473 = abs(panelWidth - keyWidth / 2)"
equation "d474 = abs(panelHeight / 2 + 3 * pitch / 4 + pitch / 4 - keyWidth / 2)"
equation "d475 = pitch / 4 + keyWidth"
equation "d476 = keyWidth"
equation "d477 = keyThickness"
equation "d479 = boardThickness"
equation "d481 = abs(panelWidth - pitch / 4)"
equation "d482 = abs(panelHeight / 2 + 3 * pitch / 4 - pitch / 4)"
equation "d483 = keyPegDiameter"
equation "d484 = -keyPegHeight"
equation "d486 = boardThickness"
equation "d488 = abs(panelWidth + pitch / 4)"
equation "d489 = abs(panelHeight / 2 + 3 * pitch / 4 + pitch / 4)"
equation "d490 = keyPegDiameter"
equation "d491 = -keyPegHeight"
equation "d493 = boardThickness"
equation "d495 = abs(panelWidth - keyWidth / 2)"
equation "d496 = abs(3 * panelHeight / 2 + 3 * pitch / 4 - pitch / 4 - keyWidth / 2)"
equation "d497 = keyWidth"
equation "d498 = pitch / 2 + keyWidth"
equation "d499 = keyThickness"
equation "d501 = boardThickness"
equation "d503 = abs(panelWidth - pitch / 4 - keyWidth / 2)"
equation "d504 = abs(3 * panelHeight / 2 + 3 * pitch / 4 - pitch / 4 - keyWidth / 2)"
equation "d505 = pitch / 4 + keyWidth"
equation "d506 = keyWidth"
equation "d507 = keyThickness"
equation "d509 = boardThickness"
equation "d511 = abs(panelWidth - keyWidth / 2)"
equation "d512 = abs(3 * panelHeight / 2 + 3 * pitch / 4 + pitch / 4 - keyWidth / 2)"
equation "d513 = pitch / 4 + keyWidth"
equation "d514 = keyWidth"
equation "d515 = keyThickness"
equation "d517 = boardThickness"
equation "d519 = abs(panelWidth - pitch / 4)"
equation "d520 = abs(3 * panelHeight / 2 + 3 * pitch / 4 - pitch / 4)"
equation "d521 = keyPegDiameter"
equation "d522 = -keyPegHeight"
equation "d524 = boardThickness"
equation "d526 = abs(panelWidth + pitch / 4)"
equation "d527 = abs(3 * panelHeight / 2 + 3 * pitch / 4 + pitch / 4)"
equation "d528 = keyPegDiameter"
equation "d529 = -keyPegHeight"
equation "d531 = frameZ"
equation "d533 = abs(mountInset - 10 mm)"
equation "d534 = abs(mountInset - 10 mm)"
equation "d536 = 2 * panelHeight - 2 * mountInset + 20 mm"
equation "d539 = frameZ"
equation "d541 = abs(mountInset - 10 mm + 7 mm)"
equation "d542 = abs(mountInset - 10 mm)"
equation "d544 = 2 * panelHeight - 2 * mountInset + 20 mm"
equation "d547 = frameZ + 1.8 mm"
equation "d549 = abs(mountInset - 10 mm + 5 mm)"
equation "d550 = abs(mountInset - 10 mm)"
equation "d552 = 2 * panelHeight - 2 * mountInset + 20 mm"
equation "d555 = frameZ"
equation "d557 = abs(panelWidth - 10 mm)"
equation "d558 = abs(mountInset - 10 mm)"
equation "d560 = 2 * panelHeight - 2 * mountInset + 20 mm"
equation "d563 = frameZ"
equation "d565 = abs(panelWidth - 10 mm + 7 mm)"
equation "d566 = abs(mountInset - 10 mm)"
equation "d568 = 2 * panelHeight - 2 * mountInset + 20 mm"
equation "d571 = frameZ + 1.8 mm"
equation "d573 = abs(panelWidth - 10 mm + 5 mm)"